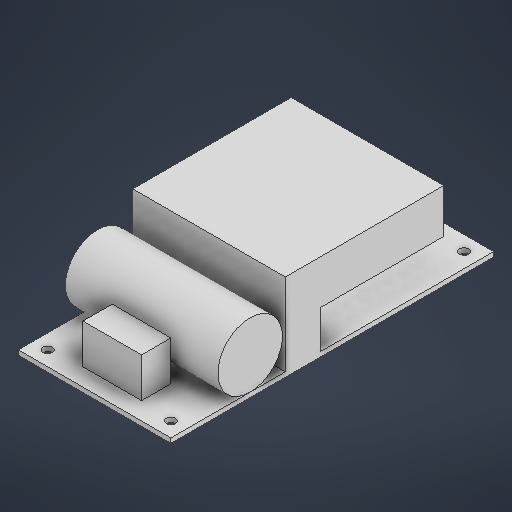
# Autodesk Inventor part: H Bridge
Saved by Autodesk Inventor 2026.2 (Build 302298010, 298A)
## iProperties
Created: 2026-05-14
Part Number: H Bridge
Material: Generic
Document SubType Name: Modeling
Designer: User
Density: 1 g/cm^3
Appearance: Default
Author: User
Autodesk Inventor part; units mm, degrees
ref_plane "YZ Plane" through (0, 0, 0) normal (1, 0, 0) x (0, 1, 0)
ref_plane "XZ Plane" through (0, 0, 0) normal (0, 1, 0) x (-1, 0, 0)
ref_plane "XY Plane" through (0, 0, 0) normal (0, 0, 1) x (1, 0, 0)
sketch "Sketch1" plane through (0, 0, 0) normal (0, 1, 0) x (-1, 0, 0)
  line L0 (26, 55) -> (-26, 55)
  line L1 (-26, 55) -> (-26, -55)
  line L2 (-26, -55) -> (26, -55)
  line L3 (26, -55) -> (26, 55)
  line L4 (26, 55) -> (-26, -55) construction
  line L5 (-26, 55) -> (26, -55) construction
  point P0 (0, 0)
  dimension "d0" = 52
  dimension "d1" = 110
  constraints: 12 end point, 2 midpoint, 2 parallel, 1 horizontal, 1 perpendicular
  measures "d0" distance of L2.end L1.end
  measures "d1" distance of L1.end L0.end
extrude "Extrusion1" add sketch "Sketch1" along normal blind 1.6
sketch "Sketch2" plane through (0, 1.6, 0) normal (0, 1, 0) x (1, 0, 0)
  line L0 (-21, 50) -> (-21, 55)
  line L1 (26, 55) -> (-26, 55) projected
  line L2 (21, 50) -> (21, 55)
  line L3 (21, -50) -> (21, -55)
  line L4 (-26, -55) -> (26, -55) projected
  line L5 (-21, -50) -> (-21, -55)
  line L6 (-21, 50) -> (-26, 50)
  line L7 (-26, 55) -> (-26, -55) projected
  line L8 (21, 50) -> (26, 50)
  line L9 (26, -55) -> (26, 55) projected
  line L10 (-21, -50) -> (-26, -50)
  line L11 (21, -50) -> (26, -50)
  point P0 (0, 0)
  dimension "d5" = 5
  dimension "d6" = 5
  dimension "d9" = 5
  dimension "d10" = 5
  dimension "d12" = 5
  dimension "d13" = 5
  dimension "d14" = 5
  dimension "d15" = 5
  constraints: 16 end point, 9 point on line, 4 coincident, 3 perpendicular, 2 horizontal, 2 vertical
  measures "d5" distance of L5.start L5.end
  measures "d6" distance of L3.start L3.end
  measures "d9" distance of L2.start L2.end
  measures "d10" distance of L0.start L0.end
  measures "d12" distance of L0.start L6.end
  measures "d13" distance of L2.start L8.end
  measures "d14" distance of L5.start L10.end
  measures "d15" distance of L3.start L11.end
hole "Hole1" at (-21, 1.6, -50) at (21, 1.6, -50) at (21, 1.6, 50) at (-21, 1.6, 50) direction (0, -1, 0) diameter 3.2 end through all
sketch "Sketch3" plane through (0, 1.6, 0) normal (0, 1, 0) x (1, 0, 0)
  line L0 (-26, 55) -> (-26, -55) projected
  line L1 (-26, 55) -> (-26, 38)
  line L2 (26, -55) -> (26, 55) projected
  line L3 (-26, 38) -> (26, 38)
  line L4 (26, 38) -> (26, -16)
  line L5 (26, -16) -> (-26, -16)
  line L6 (-26, -16) -> (-26, 38)
  point P0 (0, 0)
  point P1 (-26, 3)
  point P2 (-26, -16)
  point P3 (26, 38)
  dimension "d28" = 17
  dimension "d29" = 54
  constraints: 10 end point, 2 parallel, 2 point on line, 1 horizontal, 1 perpendicular
  measures "d28" distance of L0.start L1.end
  measures "d29" distance of L3.end L4.end
extrude "Extrusion2" add sketch "Sketch3" along normal blind 28
sketch "Sketch4" plane through (26, 0, 55) normal (1, 0, 0) x (0, 0, -1)
  line L0 (39, 1.6) -> (39, 29.6) projected
  line L1 (39, 1.6) -> (51, 1.6)
  line L2 (51, 1.6) -> (51, 14.6)
  line L3 (93, 1.6) -> (110, 1.6) projected
  line L4 (51, 14.6) -> (93, 14.6)
  line L5 (93, 14.6) -> (93, 1.6)
  line L6 (93, 1.6) -> (51, 1.6)
  line L7 (51, 1.6) -> (51, 14.6)
  point P0 (55, 0)
  dimension "d30" = 12
  dimension "d31" = 13
  constraints: 12 end point, 2 horizontal, 2 parallel, 2 perpendicular
  measures "d30" distance of L0.start L1.end
  measures "d31" distance of L1.end L2.end
extrude "Extrusion3" cut sketch "Sketch4" against normal blind 52
sketch "Sketch5" plane through (26, 0, 55) normal (1, 0, 0) x (0, 0, -1)
  line L0 (39, 1.6) -> (39, 29.6) projected
  line L1 (39, 1.6) -> (39, 12.6)
  line L2 (39, 12.6) -> (27, 12.6)
  circle A0 centre (27, 12.6) radius 11
  point P0 (55, 0)
  dimension "d34" = 11
  dimension "d35" = 12
  dimension "d36" = 22
  constraints: 4 end point, 1 centre point, 1 coincident, 1 perpendicular, 1 point on line
  measures "d34" distance of L0.start L1.end
  measures "d35" distance of L1.end L2.end
  measures "d36" diameter of A0
extrude "Extrusion4" add sketch "Sketch5" against normal blind 52
sketch "Sketch6" plane through (0, 1.6, 0) normal (0, 1, 0) x (1, 0, 0)
  line L0 (-26, -55) -> (26, -55) projected
  line L1 (0, -55) -> (0, -49)
  line L2 (0, -49) -> (10, -49)
  line L3 (10, -49) -> (10, -39)
  line L4 (26, 55) -> (-26, 55) projected
  line L5 (0, 55) -> (0, 49)
  line L6 (0, 49) -> (10, 49)
  line L7 (10, 49) -> (10, 39)
  line L8 (10, 39) -> (-10, 39)
  line L9 (-10, 39) -> (-10, 49)
  line L10 (-10, 49) -> (0, 49)
  line L11 (10, -39) -> (-10, -39)
  line L12 (-10, -39) -> (-10, -49)
  line L13 (-10, -49) -> (0, -49)
  point P0 (0, 0)
  dimension "d43" = 6
  dimension "d44" = 10
  dimension "d45" = 10
  dimension "d46" = 20
  dimension "d49" = 20
  constraints: 24 end point, 8 perpendicular, 3 vertical, 2 midpoint, 1 horizontal, 1 point on line
  measures "d43" distance of L5.start L5.end
  measures "d44" distance of L5.end L6.end
  measures "d45" distance of L6.end L7.end
  measures "d46" distance of L7.end L8.end
  measures "d49" distance of L3.end L11.end
extrude "Extrusion5" add sketch "Sketch6" along normal blind 13.5
body "Solid1"
